Low Goal (Autodesk Fusion 360 design; units mm, degrees)
part number: 2026-10-17-16-27-41-321
Autodesk Fusion 360 part; units mm, degrees
sketch "Sketch1" plane through (0, 0, 0) normal (0, 0, 1) x (1, 0, 0)
  line L0 (240, 20) -> (-240, 20)
  line L1 (-240, 20) -> (-240, -20)
  line L2 (-240, -20) -> (240, -20)
  line L3 (240, -20) -> (240, 20)
  line L4 (240, 20) -> (-240, -20) construction
  line L5 (-240, 20) -> (240, -20) construction
  dimension "d1" = 480
  dimension "d2" = 40
  constraint horizontal L0
  constraint perpendicular L0 L1
  constraint parallel L0 L2
  constraint parallel L1 L3
  constraint coincident L4 origin
  constraint coincident L5 origin
  measures "d1" distance of L1.end L2.end
  measures "d2" distance of L0.end L1.end
extrude "Extrude1" add sketch "Sketch1" along normal blind 440
sketch "Sketch2" plane through (0, 0, 440) normal (0, 0, 1) x (-1, 0, 0)
  line L0 (-240, 20) -> (-240, -20)
  line L1 (-240, -20) -> (240, -20)
  line L2 (240, -20) -> (240, 20)
  line L3 (240, 20) -> (-240, 20)
  line L4 (-200, -20) -> (200, -20)
  line L5 (200, -20) -> (200, 20)
  line L6 (200, 20) -> (-200, 20)
  line L7 (-200, 20) -> (-200, -20)
  line L8 (-200, -20) -> (200, 20) construction
  line L9 (200, -20) -> (-200, 20) construction
  dimension "d5" = 400
  constraint horizontal L4
  constraint perpendicular L4 L5
  constraint parallel L4 L6
  constraint parallel L5 L7
  constraint coincident L8 origin
  constraint coincident L9 origin
  measures "d5" distance of L5.end L6.end
extrude "Extrude2" cut sketch "Sketch2" against normal blind 400 contours L1 L3 L4 L5 L6 L7
move_body "Move1" bodies 1 to x (1, 0, 0) y (0, -1, 0) z (0, 0, -1) at (0, -40, 0)
move_body "Move2" bodies 1 to x (1, 0, 0) y (0, 1, 0) z (0, 0, 1) at (0, 0, 450)
equation "d1 = 40 cm + 8 cm"
equation "d3 = 40 cm + 4 cm"
